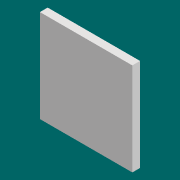
# Autodesk Inventor part: IC1
Saved by Autodesk Inventor 2022.2 (Build 262287010, 287A)
## iProperties
Created: 2024-04-23
Part Number: IC1
Material: Generic
Document SubType Name: Modeling
Designer: - LENOVO -
Density: 1 g/cm^3
Appearance: Default
Author: - LENOVO -
Autodesk Inventor part; units mm, degrees
ref_plane "YZ Plane" through (0, 0, 0) normal (1, 0, 0) x (0, 1, 0)
ref_plane "XZ Plane" through (0, 0, 0) normal (0, 1, 0) x (-1, 0, 0)
ref_plane "XY Plane" through (0, 0, 0) normal (0, 0, 1) x (1, 0, 0)
sketch "Sketch1" plane through (0, 0, 0) normal (0, 0, 1) x (1, 0, 0)
  line L0 (0.4286, -3.4623) -> (-6.7015, -3.4623)
  line L1 (-6.7015, -3.4623) -> (-6.7015, 3.6884)
  line L2 (-6.7015, 3.6884) -> (0.4286, 3.6884)
  line L3 (0.4286, 3.6884) -> (0.4286, -3.4623)
  point P0 (0, 0)
  constraints: 8 end point, 2 parallel, 1 horizontal, 1 perpendicular
extrude "Extrusion1" add sketch "Sketch1" along normal blind 0.6
body "Solid1"
